Autodesk Fusion 360 part; units mm, degrees
(part 2 of 2)
equation "d201 = mgn7_counterbore_d"
equation "d203 = mgn7_counterbore_d"
equation "d207 = mgn7_counterbore_d"
equation "d209 = mgn7_counterbore_d"
equation "d211 = mgn7_counterbore_d"
equation "d212 = mgn7_counterbore_d"
equation "d214 = mgn7_counterbore_d"
equation "d216 = mgn7_counterbore_d"
equation "d218 = mgn7_counterbore_d"
equation "d221 = -mgn7_counterbore_depth"
equation "d223 = -mgn7_counterbore_depth"
equation "mgn7h_tap_pilot_d = 1.6 mm" comment "Pilot for nominal M2 tap, simplified"
equation "mgn7h_mount_thread_depth = 2.5 mm" comment "HIWIN MGN7H block M2 thread depth"
equation "mgn7h_mount_B = 12 mm" comment "HIWIN MGN7H mounting transverse spacing"
equation "mgn7h_mount_C = 13 mm" comment "HIWIN MGN7H mounting longitudinal spacing"
equation "d231 = mgn7h_tap_pilot_d"
equation "d232 = -mgn7h_mount_thread_depth"
equation "d236 = mgn7h_tap_pilot_d"
equation "d237 = -mgn7h_mount_thread_depth"
equation "d241 = mgn7h_tap_pilot_d"
equation "d242 = -mgn7h_mount_thread_depth"
equation "d246 = mgn7h_tap_pilot_d"
equation "d247 = -mgn7h_mount_thread_depth"
equation "d251 = mgn7h_tap_pilot_d"
equation "d252 = -mgn7h_mount_thread_depth"
equation "d256 = mgn7h_tap_pilot_d"
equation "d257 = -mgn7h_mount_thread_depth"
equation "d261 = mgn7h_tap_pilot_d"
equation "d262 = -mgn7h_mount_thread_depth"
equation "d266 = mgn7h_tap_pilot_d"
equation "d267 = -mgn7h_mount_thread_depth"
equation "bridge_pad_w = 22 mm" comment "Monolithic bridge end pad width along X"
equation "bridge_pad_l = 24 mm" comment "Monolithic bridge end pad length along Y"
equation "d271 = bridge_pad_w"
equation "d272 = bridge_pad_l"
equation "d273 = bridge_pad_w / 2"
equation "d274 = x_rail_sep / 2 + bridge_pad_l / 2"
equation "d275 = bridge_h"
equation "d277 = bridge_pad_w"
equation "d278 = bridge_pad_l"
equation "d279 = bridge_pad_w / 2"
equation "d280 = x_rail_sep / 2 + bridge_pad_l / 2"
equation "d281 = bridge_h"
equation "m2_carriage_clearance_d = 2.2 mm" comment "M2 clearance in bridge and stage"
equation "d286 = m2_carriage_clearance_d"
equation "d287 = bridge_h"
equation "d291 = m2_carriage_clearance_d"
equation "d292 = bridge_h"
equation "d296 = m2_carriage_clearance_d"
equation "d297 = bridge_h"
equation "d301 = m2_carriage_clearance_d"
equation "d302 = bridge_h"
equation "d306 = m2_carriage_clearance_d"
equation "d307 = bridge_h"
equation "d311 = m2_carriage_clearance_d"
equation "d312 = bridge_h"
equation "d316 = m2_carriage_clearance_d"
equation "d317 = bridge_h"
equation "d321 = m2_carriage_clearance_d"
equation "d322 = bridge_h"
equation "d326 = m2_carriage_clearance_d"
equation "d327 = stage_t"
equation "d331 = m2_carriage_clearance_d"
equation "d332 = stage_t"
equation "d336 = m2_carriage_clearance_d"
equation "d337 = stage_t"
equation "d341 = m2_carriage_clearance_d"
equation "d342 = stage_t"
equation "d345 = m2_carriage_clearance_d"
equation "d346 = bridge_h"
equation "d349 = m2_carriage_clearance_d"
equation "d350 = bridge_h"
equation "d353 = m2_carriage_clearance_d"
equation "d354 = bridge_h"
equation "d356 = m2_carriage_clearance_d"
equation "d357 = bridge_h"
equation "d360 = m2_carriage_clearance_d"
equation "d361 = bridge_h"
equation "d364 = m2_carriage_clearance_d"
equation "d365 = bridge_h"
equation "d368 = m2_carriage_clearance_d"
equation "d369 = bridge_h"
named bodies: "CBP-1100_BASE_STOCK", "CBP-1200_COLUMN_ENVELOPE", "CBP-1210_CROSSBEAM_ENVELOPE", "CBP-2100_2MM_STAGE_STOCK", "CBP-3100_BED_SUBSTRATE_STOCK", "CBP-3110_BUILD_SURFACE_FILM", "CBP-P201_X_RAIL_ENVELOPE", "CBP-P202_X_BLOCK_UPPER_ENVELOPE", "CBP-2200_BRIDGE_STOCK", "CBP-P203_Y_RAIL_ENVELOPE", "CBP-P204_Y_BLOCK_UPPER_ENVELOPE", "CBP-1300_SHIM_STOCK"
